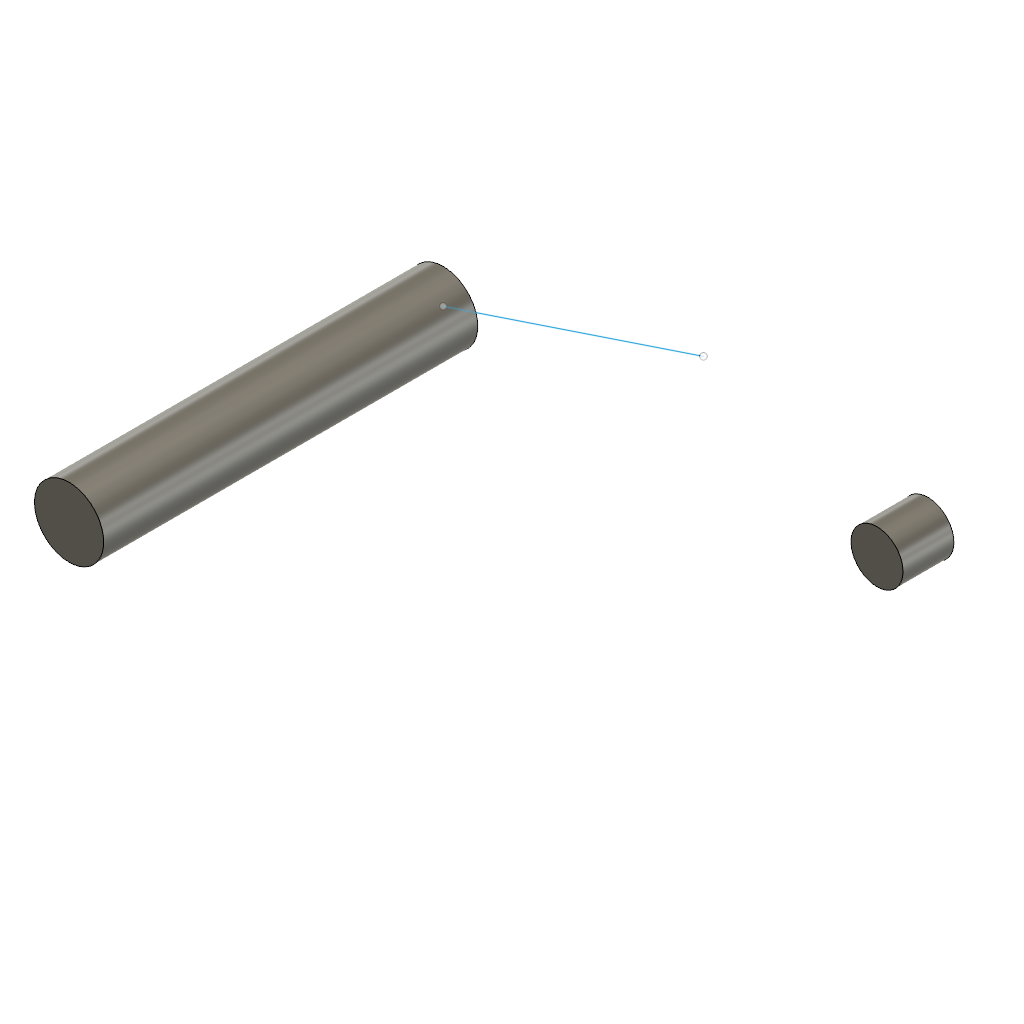
two_extrusions (Autodesk Fusion 360 design; units mm, degrees)
part number: 2026-10-20-16-46-59-828
Autodesk Fusion 360 part; units mm, degrees
sketch "UnrelatedSketch" plane through (0, 0, 0) normal (0, 1, 0) x (1, 0, 0)
  line L0 (0, 0) -> (20, 10)
sketch "IndependentProfile0" plane through (0, 0, 0) normal (0, 0, 1) x (1, 0, 0)
  circle A0 centre (0, 0) radius 4
extrude "BlindProbe_0" add sketch "IndependentProfile0" along normal blind 43.125 makes body 1
sketch "IndependentProfile1" plane through (0, 0, 0) normal (0, 0, 1) x (1, 0, 0)
  circle A0 centre (50, 0) radius 3
extrude "BlindProbe_1" add sketch "IndependentProfile1" against normal blind 5.875 separate body makes body 2
equation "d3 = -( 5.875 mm )"
